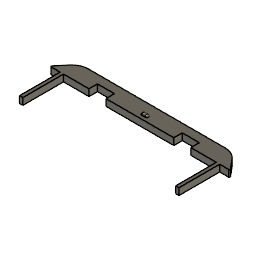
Support Bar (Autodesk Fusion 360 design; units mm, degrees)
part number: 2026-07-19-23-27-01-364
Autodesk Fusion 360 part; units mm, degrees
sketch "Sketch1" plane through (0, 0, 0) normal (0, 0, 1) x (1, 0, 0)
  line L0 (22.5, 0) -> (22.5, -12)
  line L1 (23.5, 0) -> (23.5, -12)
  line L2 (22.5, -12) -> (23.5, -12)
  line L3 (23.5, 0) -> (26.2058, 0)
  line L4 (0, 5) -> (20.145, 5)
  line L5 (26.36, 0.3274) -> (23.9998, 3.1844)
  arc A0 (26.2058, 0) -> (26.36, 0.3274) centre (26.2058, 0.2) ccw
  arc A1 (23.9998, 3.1844) -> (20.145, 5) centre (20.145, 0) ccw
  arc A2 (-26.36, 0.3274) -> (-26.2058, 0) centre (-26.2058, 0.2) ccw
  line L6 (-23.5, 0) -> (-26.2058, 0)
  line L7 (-22.5, -12) -> (-23.5, -12)
  line L8 (-23.5, 0) -> (-23.5, -12)
  line L9 (-22.5, 0) -> (-22.5, -12)
  line L10 (0, 5) -> (-20.145, 5)
  arc A3 (-20.145, 5) -> (-23.9998, 3.1844) centre (-20.145, 0) ccw
  line L11 (-26.36, 0.3274) -> (-23.9998, 3.1844)
  line L12 (-10, 2.5) -> (-15, 2.5)
  line L13 (-15, 2.5) -> (-15, 0)
  line L14 (-10, 0) -> (-10, 2.5)
  line L15 (0, 0) -> (-10, 0)
  line L16 (-15, 0) -> (-22.5, 0)
  line L17 (15, 2.5) -> (15, 0)
  line L18 (10, 2.5) -> (15, 2.5)
  line L19 (10, 0) -> (10, 2.5)
  line L20 (0, 0) -> (10, 0)
  line L21 (15, 0) -> (22.5, 0)
  constraint coincident L15.start L20.start
  constraint horizontal L20
  constraint perpendicular L0 L21
  constraint perpendicular L0 L2
  constraint perpendicular L1 L3
  constraint tangent L5 A0
  constraint tangent L3 A0
  constraint tangent L4 A1
  constraint tangent L5 A1
  constraint horizontal L12
  constraint vertical L13
  constraint vertical L14
  constraint collinear L15 L16
  constraint collinear L20 L21
extrude "Extrude8" add sketch "Sketch1" along normal blind 2
sketch "Sketch5" plane through (0, 0, 2) normal (0, 0, 1) x (-1, 0, 0)
  line L0 (-1, -1) -> (1, -1)
  line L1 (1, -1) -> (1, -2)
  line L2 (1, -2) -> (-1, -2)
  line L3 (-1, -2) -> (-1, -1)
  line L4 (1, -1.5) -> (-1, -1.5)
  point P0 (0, -1.5)
  constraint horizontal L0
  constraint perpendicular L0 L1
  constraint parallel L0 L2
  constraint parallel L1 L3
  constraint midpoint L1 L4.start
  constraint midpoint L3 L4.end
revolve "Revolve1" add sketch "Sketch5" angle 360 about axis through (-1, 1.5, 2) along (1, 0, 0) contours L1 L2 L3 L4
fillet "Fillet5" radius 0.5 2 edges at (-1, 1.5, 2.5) (1, 1.5, 2.5)
